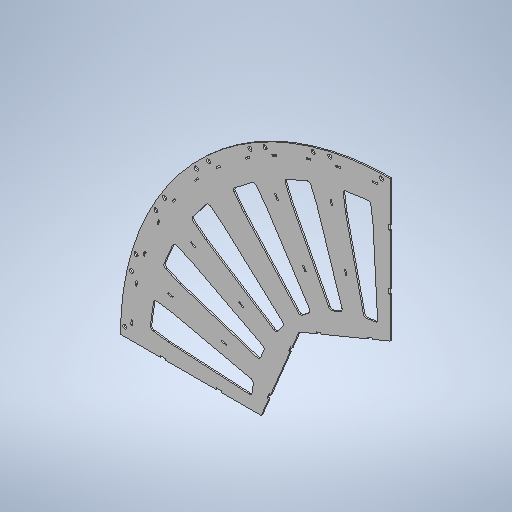
# Autodesk Inventor part: DMF-1203 Big Sector
Saved by Autodesk Inventor 2026.2 (Build 302298000, 298)
## iProperties
Created: 2024-04-30
Part Number: DMF-1203 Big Sector
Material: Stainless Steel
Document SubType Name: Sheet Metal
Designer: admin
Stock Number: DMF-1203
Density: 8 g/cm^3
Sheet Metal Rule: Default
Sheet Metal Width: 454,029 mm
Sheet Metal Length: 786,602 mm
Sheet Metal Area: 357139,769 mm^2
Appearance: Default
Flat Pattern Width: 45.4029 cm
Flat Pattern Length: 78.6602 cm
Flat Pattern Area: 3571.4 cm^2
Mass: 2673.55 g
Surface Area: 3449.14 cm^2
Volume: 334.194 cm^3
Slot1203_Width: 3,000 mm
Slot1203_Length: 10,000 mm
Chord1203_Distance: 557,000 mm
Slot1203_Spacing: 80,000 mm
Hole1203_Diameter: 9,000 mm
Rim1203_Outer_Diameter: 1166,000 mm
Author: pokla
Autodesk Inventor part; units mm, degrees
ref_plane "YZ Plane" through (0, 0, 0) normal (1, 0, 0) x (0, 1, 0)
ref_plane "XZ Plane" through (0, 0, 0) normal (0, 1, 0) x (-1, 0, 0)
ref_plane "XY Plane" through (0, 0, 0) normal (0, 0, 1) x (1, 0, 0)
sketch "Sketch1" plane through (0, 0, 0) normal (0, 0, 1) x (1, 0, 0)
  circle A0 centre (0, 0) radius 583
  line L0 (0, 0) -> (-583, 0)
  line L1 (0, 0) -> (0, 583) construction
  line L2 (0, 0) -> (0, 583)
  circle A1 centre (0, 0) radius 100
  line L3 (197.082, 197.082) -> (278.716, 0)
  line L4 (278.716, 0) -> (197.082, -197.082)
  line L5 (197.082, -197.082) -> (0, -278.716)
  line L6 (0, -278.716) -> (-197.082, -197.082)
  line L7 (-197.082, -197.082) -> (-278.716, 0)
  line L8 (-278.716, 0) -> (-197.082, 197.082)
  line L9 (-197.082, 197.082) -> (0, 278.716)
  line L10 (0, 278.716) -> (197.082, 197.082)
  point P0 (0, 0)
  point P1 (0, 0)
  point P2 (0, 0)
  point P3 (0, 0)
  point P4 (-100, 0)
  point P5 (0, 100)
  point P6 (0, 278.716)
  point P7 (-278.716, 0)
  point P8 (0, 278.716)
  point P9 (-278.716, 0)
  dimension "d30" = 90
  dimension "d31" = 1166
  dimension "d65" = 90
  dimension "d66" = 200
  dimension "d91" = 515
  measures "d30" angle of L2 L0
  measures "d31" diameter of A0
  measures "d65" angle of L1 L0
  measures "d66" diameter of A1
  measures "d91" distance between parallel lines of L5 L9
extrude "Plate1" add sketch "Sketch1" against normal blind 3 contours L2 L9 L8 L0 A0
sketch "Sketch3" plane through (0, 0, -3) normal (0, 0, -1) x (-1, 0, 0)
  arc A0 (583, 0) -> (0, 583) centre (0, 0) ccw projected
  line L0 (69.5866, 495.134) -> (0, 0) construction
  line L1 (42.662, 519.1146) -> (37.095, 479.5039)
  line L2 (37.095, 479.5039) -> (96.5111, 471.1535)
  line L3 (96.5111, 471.1535) -> (102.0781, 510.7642)
  line L4 (102.0781, 510.7642) -> (42.662, 519.1146)
  line L5 (42.662, 519.1146) -> (96.5111, 471.1535) construction
  line L6 (37.095, 479.5039) -> (102.0781, 510.7642) construction
  line L7 (0, 0) -> (318.1981, 318.1981) construction
  circle A1 centre (0, 0) radius 500 construction
  line L8 (96.5111, 471.1535) -> (56.606, 294.9928)
  line L9 (56.606, 294.9928) -> (26.8979, 299.168)
  line L10 (26.8979, 299.168) -> (37.095, 479.5039)
  line L11 (0, 278.716) -> (0, 583) projected
  line L12 (197.082, 197.082) -> (0, 278.716) projected
  line L13 (278.716, 0) -> (197.082, 197.082) projected
  line L14 (583, 0) -> (278.716, 0) projected
  point P0 (66.8031, 475.3287)
  point P1 (41.7519, 297.0804)
  dimension "d57" = 1000
  dimension "d53" = 37
  dimension "d55" = 60
  dimension "d56" = 40
  dimension "d150" = 180
  dimension "d151" = 30
  constraints: 22 end point, 4 midpoint, 2 parallel, 2 perpendicular, 2 point on line, 1 coincident, 3 other
  measures "d53" angle of L0 L7
  measures "d55" distance of L3.end L1.start
  measures "d56" distance of L2.end L3.end
  measures "d150" distance between parallel lines of L9 L2
  measures "d151" distance of L8.end L9.end
extrude "Cut1" cut sketch "Sketch3" against normal blind 3 contours L4 L3 L2 L1 | L2 L8 L9 L10
sketch "Sketch2" plane through (0, 0, 0) normal (0, 0, 1) x (1, 0, 0)
  circle A0 centre (0, 0) radius 574
  arc A1 (0, 583) -> (-583, 0) centre (0, 0) ccw projected
  line L0 (0, 0) -> (0, 583) construction
  line L1 (0, 0) -> (-18.7808, 573.6927) construction
  line L2 (-130.3418, 559.0054) -> (0, 0) construction
  line L3 (0, 0) -> (0, 574) construction
  line L4 (0, 0) -> (18.7808, 573.6927) construction
  line L5 (0, 0) -> (130.3418, 559.0054) construction
  line L6 (0, 0) -> (-166.6234, 549.2838) construction
  line L7 (0, 0) -> (-270.5817, 506.2228) construction
  dimension "d34" = 1148
  dimension "d35" = 1.875
  dimension "d36" = 11.25
  dimension "d44" = 1.875
  dimension "d45" = 11.25
  dimension "d49" = 3.75
  dimension "d50" = 11.25
  constraints: 16 end point, 3 coincident, 1 vertical, 9 other
  measures "d35" angle of L0 L1
  measures "d36" angle of L1 L2
  measures "d44" angle of L4 L3
  measures "d45" angle of L5 L4
  measures "d49" angle of L2 L6
  measures "d50" angle of L6 L7
hole "Hole1" at (-18.7808, 573.6927, 0) at (-130.3418, 559.0054, 0) at (130.3418, 559.0054, 0) at (18.7808, 573.6927, 0) at (-166.6234, 549.2838, 0) at (-270.5817, 506.2228, 0) direction (0, 0, -1) diameter 9 end through all
pattern_circular "Circular Pattern1" count 4 over 90 about axis through (0, 0, -10) along (0, 0, 1) of "Hole1"
fillet "Corner Round1" radius 6 6 edges at (-42.662, 519.1146, -1.5) (-37.095, 479.5039, -1.5) (-102.0781, 510.7642, -1.5) (-96.5111, 471.1535, -1.5) (-56.606, 294.9928, -1.5) (-26.8979, 299.168, -1.5)
pattern_circular "Circular Pattern2" count 6 over 74 about axis through (0, 0, -10) along (0, 0, 1) of "Cut1", "Corner Round1"
sketch "Sketch15" plane through (0, 0, 0) normal (0, 0, 1) x (1, 0, 0)
  line L0 (-558.1085, 28.0881) -> (-556.8032, 38.0025)
  line L1 (-556.8032, 38.0025) -> (-559.7775, 38.3941)
  line L2 (-559.7775, 38.3941) -> (-561.0828, 28.4796)
  line L3 (-561.0828, 28.4796) -> (-558.1085, 28.0881)
  line L4 (-547.6664, 107.4037) -> (-546.3611, 117.3181)
  line L5 (-546.3611, 117.3181) -> (-549.3354, 117.7097)
  line L6 (-549.3354, 117.7097) -> (-550.6407, 107.7952)
  line L7 (-550.6407, 107.7952) -> (-547.6664, 107.4037)
  line L8 (-564.8322, 0) -> (-545.586, 146.1893)
  line L9 (-545.586, 146.1893) -> (-489.159, 282.4161)
  line L10 (-489.159, 282.4161) -> (-399.3967, 399.3967)
  line L11 (-399.3967, 399.3967) -> (-282.4161, 489.159)
  line L12 (-282.4161, 489.159) -> (-146.1893, 545.586)
  line L13 (-146.1893, 545.586) -> (0, 564.8322)
  line L14 (0, 564.8322) -> (146.1893, 545.586)
  line L15 (146.1893, 545.586) -> (282.4161, 489.159)
  line L16 (282.4161, 489.159) -> (399.3967, 399.3967)
  line L17 (399.3967, 399.3967) -> (489.159, 282.4161)
  line L18 (489.159, 282.4161) -> (545.586, 146.1893)
  line L19 (545.586, 146.1893) -> (564.8322, 0)
  line L20 (564.8322, 0) -> (545.586, -146.1893)
  line L21 (545.586, -146.1893) -> (489.159, -282.4161)
  line L22 (489.159, -282.4161) -> (399.3967, -399.3967)
  line L23 (399.3967, -399.3967) -> (282.4161, -489.159)
  line L24 (282.4161, -489.159) -> (146.1893, -545.586)
  line L25 (146.1893, -545.586) -> (0, -564.8322)
  line L26 (0, -564.8322) -> (-146.1893, -545.586)
  line L27 (-146.1893, -545.586) -> (-282.4161, -489.159)
  line L28 (-282.4161, -489.159) -> (-399.3967, -399.3967)
  line L29 (-399.3967, -399.3967) -> (-489.159, -282.4161)
  line L30 (-489.159, -282.4161) -> (-545.586, -146.1893)
  line L31 (-545.586, -146.1893) -> (-564.8322, 0)
  circle A0 centre (0, 0) radius 564.8322
  line L32 (0, 0) -> (-555.2091, 73.0947) construction
  point P0 (-560.4302, 33.4369)
  point P1 (-549.9881, 112.7525)
  dimension "d182" = 10
  dimension "d183" = 3
  dimension "d195" = 560
  dimension "d196" = 147.4508
  dimension "d197" = 80
  constraints: 66 end point, 4 parallel, 3 midpoint, 2 coincident, 2 collinear, 2 equal length, 2 horizontal alignment, 2 perpendicular, 1 symmetric about line, 51 other
  measures "d182" distance of L4.start L4.end
  measures "d183" distance of L4.end L5.end
  measures "d195" distance from line of L32.start L8
  measures "d196" distance of L8.start L8.end
  measures "d197" distance of point (-560.43, 33.437) point (-549.988, 112.752)
extrude "Cut4" cut sketch "Sketch15" against normal blind 3 contours L3 L2 L1 L0 | L6 L5 L4 L7
pattern_circular "Circular Pattern4" count 6 over 75 about axis through (0, 0, -10) along (0, 0, -1) of "Cut4"
sketch "Sketch Slots Spokes" plane through (0, 0, 0) normal (0, 0, 1) x (1, 0, 0)
  line L0 (0, 485.358) -> (0, 496.358)
  line L1 (0, 496.358) -> (-3, 496.358)
  line L2 (-3, 496.358) -> (-3, 485.358)
  line L3 (-3, 485.358) -> (0, 485.358)
  line L4 (0, 365.358) -> (0, 376.358)
  line L5 (0, 376.358) -> (-3, 376.358)
  line L6 (-3, 376.358) -> (-3, 365.358)
  line L7 (-3, 365.358) -> (0, 365.358)
  line L8 (-365.358, 0) -> (-376.358, 0)
  line L9 (-376.358, 0) -> (-376.358, 3)
  line L10 (-376.358, 3) -> (-365.358, 3)
  line L11 (-365.358, 3) -> (-365.358, 0)
  line L12 (-485.358, 0) -> (-496.358, 0)
  line L13 (-496.358, 0) -> (-496.358, 3)
  line L14 (-496.358, 3) -> (-485.358, 3)
  line L15 (-485.358, 3) -> (-485.358, 0)
  line L16 (-184.3368, 316.3189) -> (-189.8377, 325.8446)
  line L17 (-189.8377, 325.8446) -> (-187.2398, 327.3448)
  line L18 (-187.2398, 327.3448) -> (-181.7389, 317.8191)
  line L19 (-181.7389, 317.8191) -> (-184.3368, 316.3189)
  line L20 (-244.3469, 420.236) -> (-249.8479, 429.7618)
  line L21 (-249.8479, 429.7618) -> (-247.2499, 431.262)
  line L22 (-247.2499, 431.262) -> (-241.749, 421.7363)
  line L23 (-241.749, 421.7363) -> (-244.3469, 420.236)
  line L24 (-354.017, 93.3254) -> (-364.6425, 96.1714)
  line L25 (-364.6425, 96.1714) -> (-363.8663, 99.0692)
  line L26 (-363.8663, 99.0692) -> (-353.2408, 96.2233)
  line L27 (-353.2408, 96.2233) -> (-354.017, 93.3254)
  line L28 (-469.9311, 124.3724) -> (-480.5566, 127.2184)
  line L29 (-480.5566, 127.2184) -> (-479.7804, 130.1162)
  line L30 (-479.7804, 130.1162) -> (-469.155, 127.2702)
  line L31 (-469.155, 127.2702) -> (-469.9311, 124.3724)
  line L32 (-316.3191, 184.3369) -> (-325.8449, 189.8379)
  line L33 (-325.8449, 189.8379) -> (-327.3451, 187.2399)
  line L34 (-327.3451, 187.2399) -> (-317.8194, 181.739)
  line L35 (-317.8194, 181.739) -> (-316.3191, 184.3369)
  line L36 (-420.2363, 244.3471) -> (-429.7621, 249.848)
  line L37 (-429.7621, 249.848) -> (-431.2623, 247.2501)
  line L38 (-431.2623, 247.2501) -> (-421.7366, 241.7491)
  line L39 (-421.7366, 241.7491) -> (-420.2363, 244.3471)
  line L40 (-93.3255, 354.0173) -> (-96.1715, 364.6427)
  line L41 (-96.1715, 364.6427) -> (-99.0693, 363.8666)
  line L42 (-99.0693, 363.8666) -> (-96.2234, 353.2411)
  line L43 (-96.2234, 353.2411) -> (-93.3255, 354.0173)
  line L44 (-124.3725, 469.9314) -> (-127.2184, 480.5569)
  line L45 (-127.2184, 480.5569) -> (-130.1163, 479.7807)
  line L46 (-130.1163, 479.7807) -> (-127.2703, 469.1552)
  line L47 (-127.2703, 469.1552) -> (-124.3725, 469.9314)
  line L48 (-262.7122, 38.6366) -> (-258.8853, 47.8754)
  line L49 (-258.8853, 47.8754) -> (-261.657, 49.0235)
  line L50 (-261.657, 49.0235) -> (-265.4838, 39.7847)
  line L51 (-265.4838, 39.7847) -> (-262.7122, 38.6366)
  line L52 (-262.7122, 38.6366) -> (-261.657, 49.0235) construction
  line L53 (-258.8853, 47.8754) -> (-265.4838, 39.7847) construction
  line L54 (-278.716, 0) -> (-197.082, 197.082) construction
  line L55 (-197.082, 197.082) -> (0, 278.716) construction
  line L56 (-212.9633, 158.741) -> (-216.7902, 149.5022)
  line L57 (-216.7902, 149.5022) -> (-219.5618, 150.6502)
  line L58 (-219.5618, 150.6502) -> (-215.735, 159.889)
  line L59 (-215.735, 159.889) -> (-212.9633, 158.741)
  line L60 (-212.9633, 158.741) -> (-219.5618, 150.6502) construction
  line L61 (-216.7902, 149.5022) -> (-215.735, 159.889) construction
  line L62 (-197.082, 197.082) -> (-203.655, 203.655) construction
  line L63 (-38.6366, 262.7122) -> (-47.8754, 258.8853)
  line L64 (-47.8754, 258.8853) -> (-49.0235, 261.657)
  line L65 (-49.0235, 261.657) -> (-39.7847, 265.4838)
  line L66 (-39.7847, 265.4838) -> (-38.6366, 262.7122)
  line L67 (-38.6366, 262.7122) -> (-49.0235, 261.657) construction
  line L68 (-47.8754, 258.8853) -> (-39.7847, 265.4838) construction
  line L69 (-158.741, 212.9633) -> (-149.5022, 216.7902)
  line L70 (-149.5022, 216.7902) -> (-150.6502, 219.5618)
  line L71 (-150.6502, 219.5618) -> (-159.889, 215.735)
  line L72 (-159.889, 215.735) -> (-158.741, 212.9633)
  line L73 (-158.741, 212.9633) -> (-150.6502, 219.5618) construction
  line L74 (-149.5022, 216.7902) -> (-159.889, 215.735) construction
  line L75 (-98.541, 237.899) -> (-94.7141, 228.6602)
  point P0 (-262.1846, 43.8301)
  point P1 (-216.2626, 154.6956)
  point P2 (-262.1846, 43.8301)
  point P3 (-216.2626, 154.6956)
  point P4 (-43.8301, 262.1846)
  point P5 (-154.6956, 216.2626)
  point P6 (-43.8301, 262.1846)
  point P7 (-154.6956, 216.2626)
  dimension "d200" = 10
  dimension "d201" = 3
  dimension "d202" = 120
  dimension "d203" = 112.5
  dimension "d204" = 112.5
  dimension "d205" = 41.5
  constraints: 148 end point, 12 symmetric about line, 10 midpoint, 8 horizontal, 8 vertical, 4 parallel, 3 collinear, 2 equal length, 2 perpendicular, 32 other
  measures "d200" distance of L49.end L50.end
  measures "d201" distance of L48.end L49.end
  measures "d202" distance of point (-262.185, 43.83) point (-216.263, 154.696)
  measures "d203" angle of L54 L62
  measures "d204" angle of L55 L62
  measures "d205" distance from line of L54.end L59
extrude "Cut Slots Spokes" cut sketch "Sketch Slots Spokes" against normal blind 3
equation "\"d91\" = Барабан_размер_по_плоскостям"
equation "\"d59\" = Thickness"
equation "\"d44\" = d35"
equation "\"d45\" = d36"
equation "\"d49\" = 2 * d35"
equation "\"d50\" = d36"
equation "\"d42\" = Thickness"
equation "\"d15\" = Thickness"
equation "\"BendRadius\" = Thickness"
equation "\"BendReliefWidth\" = Thickness"
equation "\"CornerReliefSize\" = 4 * Thickness"
equation "\"MinimumRemnant\" = 2 * Thickness"
equation "\"TransitionRadius\" = BendRadius"
equation "\"JacobiRadiusSize\" = BendRadius"
equation "\"GapSize\" = Thickness"
equation "\"Slot1203_Width\" = 3"
equation "\"Chord1203_Distance\" = 557"
equation "\"Hole1203_Diameter\" = 9"
equation "\"Rim1203_Outer_Diameter\" = 1166"
equation "\"Барабан_размер_по_плоскостям\" = 515"
equation "\"Thickness\" = 3"
body "Solid1"
